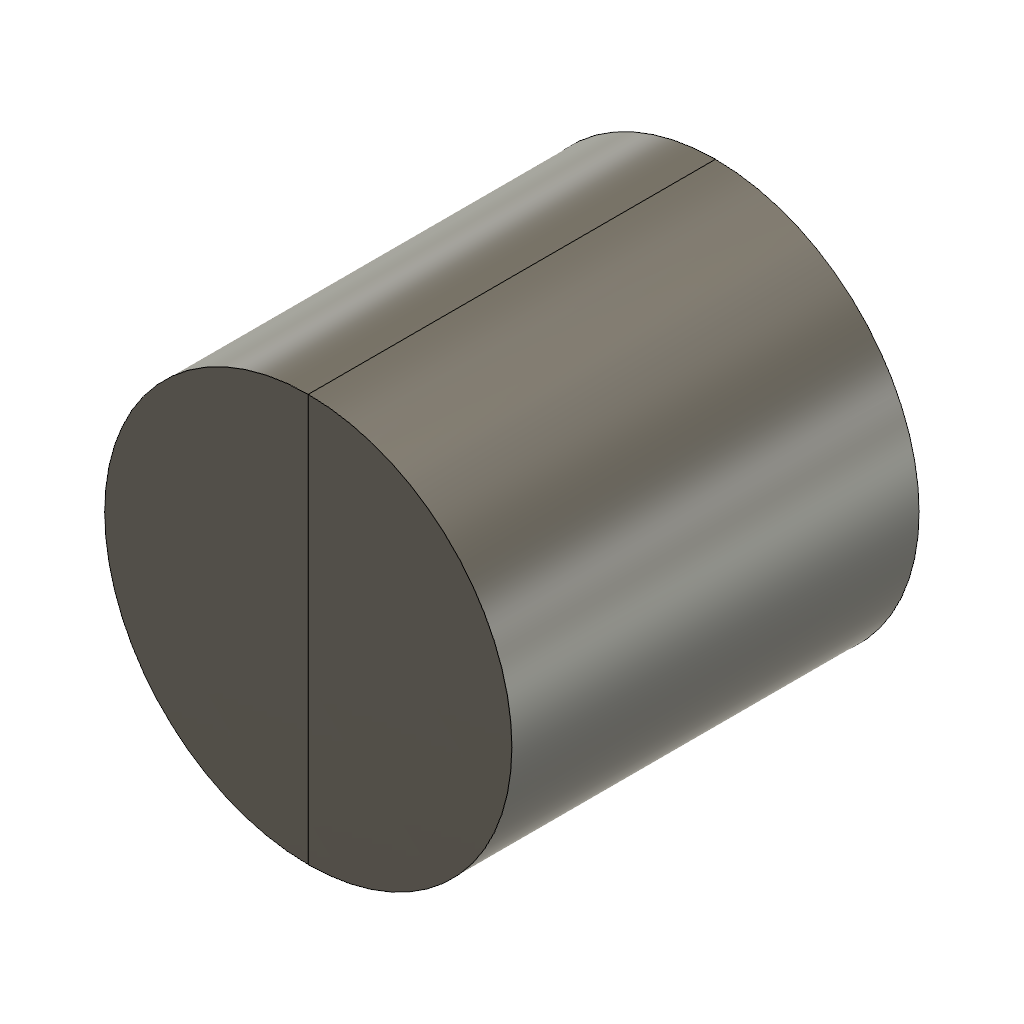
SplitBody (Autodesk Fusion 360 design; units mm, degrees)
part number: 2026-10-20-18-19-57-220
Autodesk Fusion 360 part; units mm, degrees
sketch "SeedProfile" plane through (0, 0, 0) normal (0, 0, 1) x (1, 0, 0)
  circle A0 centre (0, 0) radius 10
extrude "SeedExtrusion" add sketch "SeedProfile" along normal blind 20 makes body 1
split "ProbeSplitBody" by plane through (0, 0, 0) normal (1, 0, 0) bodies 1 makes body 2 at (0.4758, 9.9887, 13.3333)
